710000_P01_ELECTRICAL_CAD (Autodesk Fusion 360 design; units mm, degrees)
description: ELECTRICAL | Điện | P01 | routes, pockets, grommets, power unit, hub zone
part number: 2026-10-31-23-39-13-770
description: ELECTRICAL - POWER UNIT - B2 | Điện - hộp nguồn - vách sau B2 | HS | P01
part number: 710001
description: ELECTRICAL - HARNESS - LIGHT FEED - B2/B4 | Điện - bó dây cấp đèn - vách sau | HS | P01
part number: 710011
description: ELECTRICAL - HARNESS - TRUNK - B2/R1 | Điện - bó dây chính - vách sau và vách phải | HS | P01
part number: 710021
description: ELECTRICAL - HARNESS - AIR COLUMN | Điện - bó dây cột gió | HS | P01
part number: 710023
description: ELECTRICAL - HARNESS - CALL LIGHT - R2 | Điện - bó dây đèn gọi video - vách phải trên | HS | P01
part number: 710024
description: ELECTRICAL - DRAW WIRE - CEILING ROUTE | Điện - dây mồi - đường trần | HS | P01
part number: 710031
description: ELECTRICAL - HUB AND CONTROLS ZONE | Điện - vùng cảm biến và nút bấm | HS | P01
part number: 710041
Autodesk Fusion 360 part; units mm, degrees
(part 1 of 2)
sketch "OUTLINE - PU" plane through (0, 0, 0) normal (0, 0, 1) x (1, 0, 0) in component "710001 ELECTRICAL - POWER UNIT - B2"
  line L0 (95, 766) -> (391, 766)
  line L1 (391, 766) -> (391, 838)
  line L2 (391, 838) -> (95, 838)
  line L3 (95, 838) -> (95, 766)
  dimension "d1608" = 296
  dimension "d1610" = 95
  dimension "d1611" = 766
  constraint horizontal L0
  constraint vertical L1
  constraint horizontal L2
  constraint vertical L3
  measures "d1608" horizontal distance of L0.start L0.end
  measures "d1610" horizontal distance of origin L0.start
  measures "d1611" vertical distance of origin L0.start
extrude "EXTRUDE - PU" add sketch "OUTLINE - PU" along normal blind 260 from surface at 870 makes body 1 in component "710001 ELECTRICAL - POWER UNIT - B2"
sketch "OUTLINE - PU-PLATE" plane through (0, 0, 0) normal (0, 0, 1) x (1, 0, 0) in component "710001 ELECTRICAL - POWER UNIT - B2"
  line L0 (83, 762.5) -> (403, 762.5)
  line L1 (403, 762.5) -> (403, 764)
  line L2 (403, 764) -> (83, 764)
  line L3 (83, 764) -> (83, 762.5)
  dimension "d1615" = 320
  dimension "d1617" = 83
  dimension "d1618" = 762.5
  constraint horizontal L0
  constraint vertical L1
  constraint horizontal L2
  constraint vertical L3
  measures "d1615" horizontal distance of L0.start L0.end
  measures "d1617" horizontal distance of origin L0.start
  measures "d1618" vertical distance of origin L0.start
extrude "EXTRUDE - PU-PLATE" add sketch "OUTLINE - PU-PLATE" along normal blind 284 from surface at 858 separate body makes body 2 in component "710001 ELECTRICAL - POWER UNIT - B2"
sketch "OUTLINE - INLET" plane through (0, 0, 0) normal (0, 1, 0) x (1, 0, 0) in component "710001 ELECTRICAL - POWER UNIT - B2"
  circle A0 centre (120, -313) radius 12
  dimension "d1622" = 24
  dimension "d1623" = 120
  dimension "d1624" = 313
  measures "d1622" diameter of A0
  measures "d1623" horizontal distance of origin A0.centre
  measures "d1624" vertical distance of origin A0.centre
extrude "EXTRUDE - INLET" add sketch "OUTLINE - INLET" along normal blind 35 from surface at 815 separate body makes body 3 in component "710001 ELECTRICAL - POWER UNIT - B2"
sketch "OUTLINE - LAN-FT" plane through (0, 0, 0) normal (0, 1, 0) x (1, 0, 0) in component "710001 ELECTRICAL - POWER UNIT - B2"
  circle A0 centre (120, -375) radius 12
  dimension "d1628" = 24
  dimension "d1629" = 120
  dimension "d1630" = 375
  measures "d1628" diameter of A0
  measures "d1629" horizontal distance of origin A0.centre
  measures "d1630" vertical distance of origin A0.centre
extrude "EXTRUDE - LAN-FT" add sketch "OUTLINE - LAN-FT" along normal blind 35 from surface at 815 separate body makes body 4 in component "710001 ELECTRICAL - POWER UNIT - B2"
sketch "OUTLINE - SLEEVE" plane through (0, 0, 0) normal (0, 0, 1) x (1, 0, 0) in component "710001 ELECTRICAL - POWER UNIT - B2"
  line L0 (140, 810) -> (160, 810)
  line L1 (160, 810) -> (160, 830)
  line L2 (160, 830) -> (140, 830)
  line L3 (140, 830) -> (140, 810)
  dimension "d1634" = 20
  dimension "d1635" = 20
  dimension "d1636" = 140
  dimension "d1637" = 810
  constraint horizontal L0
  constraint vertical L1
  constraint horizontal L2
  constraint vertical L3
  measures "d1634" horizontal distance of L0.start L0.end
  measures "d1635" vertical distance of L0.start L2.end
  measures "d1636" horizontal distance of origin L0.start
  measures "d1637" vertical distance of origin L0.start
extrude "EXTRUDE - SLEEVE" add sketch "OUTLINE - SLEEVE" along normal blind 569 from surface at 301 separate body makes body 5 in component "710001 ELECTRICAL - POWER UNIT - B2"
sketch "OUTLINE - P5" plane through (0, 0, 0) normal (0, 0, 1) x (1, 0, 0) in component "710011 ELECTRICAL - HARNESS - LIGHT FEED - B2/B4"
  line L0 (306, 779.5) -> (386, 779.5)
  line L1 (386, 779.5) -> (386, 795.5)
  line L2 (386, 795.5) -> (306, 795.5)
  line L3 (306, 795.5) -> (306, 779.5)
  dimension "d1643" = 306
  dimension "d1644" = 779.5
  constraint horizontal L0
  constraint vertical L1
  constraint horizontal L2
  constraint vertical L3
  measures "d1643" horizontal distance of origin L0.start
  measures "d1644" vertical distance of origin L0.start
extrude "EXTRUDE - P5" add sketch "OUTLINE - P5" along normal blind 80 from surface at 1134.5 separate body makes body 6 in component "710011 ELECTRICAL - HARNESS - LIGHT FEED - B2/B4"
sketch "OUTLINE - L1-B2" plane through (0, 0, 0) normal (0, 0, 1) x (1, 0, 0) in component "710011 ELECTRICAL - HARNESS - LIGHT FEED - B2/B4"
  line L0 (338, 779.5) -> (354, 779.5)
  line L1 (354, 779.5) -> (354, 795.5)
  line L2 (354, 795.5) -> (338, 795.5)
  line L3 (338, 795.5) -> (338, 779.5)
  dimension "d1650" = 338
  dimension "d1651" = 779.5
  constraint horizontal L0
  constraint vertical L1
  constraint horizontal L2
  constraint vertical L3
  measures "d1650" horizontal distance of origin L0.start
  measures "d1651" vertical distance of origin L0.start
extrude "EXTRUDE - L1-B2" add sketch "OUTLINE - L1-B2" along normal blind 15.87 from surface at 1214.5 separate body makes body 7 in component "710011 ELECTRICAL - HARNESS - LIGHT FEED - B2/B4"
sketch "OUTLINE - G-B2-B4" plane through (0, 0, 0) normal (0, 0, 1) x (1, 0, 0) in component "710011 ELECTRICAL - HARNESS - LIGHT FEED - B2/B4"
  circle A0 centre (346, 787.5) radius 9.55
  dimension "d1655" = 19.1
  dimension "d1656" = 346
  dimension "d1657" = 787.5
  measures "d1655" diameter of A0
  measures "d1656" horizontal distance of origin A0.centre
  measures "d1657" vertical distance of origin A0.centre
extrude "EXTRUDE - G-B2-B4" add sketch "OUTLINE - G-B2-B4" along normal blind 3.26 from surface at 1230.37 separate body makes body 8 in component "710011 ELECTRICAL - HARNESS - LIGHT FEED - B2/B4"
sketch "OUTLINE - P4" plane through (0, 0, 0) normal (0, 0, 1) x (1, 0, 0) in component "710011 ELECTRICAL - HARNESS - LIGHT FEED - B2/B4"
  line L0 (306, 779.5) -> (386, 779.5)
  line L1 (386, 779.5) -> (386, 795.5)
  line L2 (386, 795.5) -> (306, 795.5)
  line L3 (306, 795.5) -> (306, 779.5)
  dimension "d1663" = 306
  dimension "d1664" = 779.5
  constraint horizontal L0
  constraint vertical L1
  constraint horizontal L2
  constraint vertical L3
  measures "d1663" horizontal distance of origin L0.start
  measures "d1664" vertical distance of origin L0.start
extrude "EXTRUDE - P4" add sketch "OUTLINE - P4" along normal blind 150 from surface at 1233.63 separate body makes body 9 in component "710011 ELECTRICAL - HARNESS - LIGHT FEED - B2/B4"
sketch "OUTLINE - L1-B4" plane through (0, 0, 0) normal (0, 0, 1) x (1, 0, 0) in component "710011 ELECTRICAL - HARNESS - LIGHT FEED - B2/B4"
  line L0 (338, 779.5) -> (354, 779.5)
  line L1 (354, 779.5) -> (354, 795.5)
  line L2 (354, 795.5) -> (338, 795.5)
  line L3 (338, 795.5) -> (338, 779.5)
  dimension "d1670" = 338
  dimension "d1671" = 779.5
  constraint horizontal L0
  constraint vertical L1
  constraint horizontal L2
  constraint vertical L3
  measures "d1670" horizontal distance of origin L0.start
  measures "d1671" vertical distance of origin L0.start
extrude "EXTRUDE - L1-B4" add sketch "OUTLINE - L1-B4" along normal blind 806.37 from surface at 1383.63 separate body makes body 10 in component "710011 ELECTRICAL - HARNESS - LIGHT FEED - B2/B4"
sketch "OUTLINE - P6" plane through (0, 0, 0) normal (0, 0, 1) x (1, 0, 0) in component "710011 ELECTRICAL - HARNESS - LIGHT FEED - B2/B4"
  line L0 (306, 779.5) -> (386, 779.5)
  line L1 (386, 779.5) -> (386, 795.5)
  line L2 (386, 795.5) -> (306, 795.5)
  line L3 (306, 795.5) -> (306, 779.5)
  dimension "d1677" = 306
  dimension "d1678" = 779.5
  constraint horizontal L0
  constraint vertical L1
  constraint horizontal L2
  constraint vertical L3
  measures "d1677" horizontal distance of origin L0.start
  measures "d1678" vertical distance of origin L0.start
extrude "EXTRUDE - P6" add sketch "OUTLINE - P6" along normal blind 100 from surface at 2190 separate body makes body 11 in component "710011 ELECTRICAL - HARNESS - LIGHT FEED - B2/B4"
sketch "OUTLINE - FX-SHELF" plane through (0, 0, 0) normal (0, 1, 0) x (1, 0, 0) in component "710011 ELECTRICAL - HARNESS - LIGHT FEED - B2/B4"
  circle A0 centre (346, -2250) radius 8
  dimension "d1682" = 16
  dimension "d1683" = 346
  dimension "d1684" = 2250
  measures "d1682" diameter of A0
  measures "d1683" horizontal distance of origin A0.centre
  measures "d1684" vertical distance of origin A0.centre
extrude "EXTRUDE - FX-SHELF" add sketch "OUTLINE - FX-SHELF" along normal blind 9.5 from surface at 766 separate body makes body 12 in component "710011 ELECTRICAL - HARNESS - LIGHT FEED - B2/B4"
sketch "OUTLINE - P1" plane through (0, 0, 0) normal (0, 0, 1) x (1, 0, 0) in component "710021 ELECTRICAL - HARNESS - TRUNK - B2/R1"
  line L0 (395.5, 779.5) -> (545.5, 779.5)
  line L1 (545.5, 779.5) -> (545.5, 795.5)
  line L2 (545.5, 795.5) -> (395.5, 795.5)
  line L3 (395.5, 795.5) -> (395.5, 779.5)
  dimension "d1688" = 150
  dimension "d1690" = 395.5
  dimension "d1691" = 779.5
  constraint horizontal L0
  constraint vertical L1
  constraint horizontal L2
  constraint vertical L3
  measures "d1688" horizontal distance of L0.start L0.end
  measures "d1690" horizontal distance of origin L0.start
  measures "d1691" vertical distance of origin L0.start
extrude "EXTRUDE - P1" add sketch "OUTLINE - P1" along normal blind 80 from surface at 1060 separate body makes body 13 in component "710021 ELECTRICAL - HARNESS - TRUNK - B2/R1"
sketch "OUTLINE - T1-B2" plane through (0, 0, 0) normal (0, 0, 1) x (1, 0, 0) in component "710021 ELECTRICAL - HARNESS - TRUNK - B2/R1"
  line L0 (545.5, 779.5) -> (1163.5, 779.5)
  line L1 (1163.5, 779.5) -> (1163.5, 795.5)
  line L2 (1163.5, 795.5) -> (545.5, 795.5)
  line L3 (545.5, 795.5) -> (545.5, 779.5)
  dimension "d1695" = 618
  dimension "d1697" = 545.5
  dimension "d1698" = 779.5
  constraint horizontal L0
  constraint vertical L1
  constraint horizontal L2
  constraint vertical L3
  measures "d1695" horizontal distance of L0.start L0.end
  measures "d1697" horizontal distance of origin L0.start
  measures "d1698" vertical distance of origin L0.start
extrude "EXTRUDE - T1-B2" add sketch "OUTLINE - T1-B2" along normal blind 30 from surface at 1085 separate body makes body 14 in component "710021 ELECTRICAL - HARNESS - TRUNK - B2/R1"
sketch "OUTLINE - FS-CNR" plane through (0, 0, 0) normal (0, 0, 1) x (1, 0, 0) in component "710021 ELECTRICAL - HARNESS - TRUNK - B2/R1"
  line L0 (1166, 768) -> (1175.5, 768)
  line L1 (1175.5, 768) -> (1175.5, 786)
  line L2 (1175.5, 786) -> (1166, 786)
  line L3 (1166, 786) -> (1166, 768)
  dimension "d1703" = 18
  dimension "d1704" = 1166
  dimension "d1705" = 768
  constraint horizontal L0
  constraint vertical L1
  constraint horizontal L2
  constraint vertical L3
  measures "d1703" vertical distance of L0.start L2.end
  measures "d1704" horizontal distance of origin L0.start
  measures "d1705" vertical distance of origin L0.start
extrude "EXTRUDE - FS-CNR" add sketch "OUTLINE - FS-CNR" along normal blind 120 from surface at 1040 separate body makes body 15 in component "710021 ELECTRICAL - HARNESS - TRUNK - B2/R1"
sketch "OUTLINE - P2" plane through (0, 0, 0) normal (0, 0, 1) x (1, 0, 0) in component "710021 ELECTRICAL - HARNESS - TRUNK - B2/R1"
  line L0 (1179.5, 637) -> (1195.5, 637)
  line L1 (1195.5, 637) -> (1195.5, 787)
  line L2 (1195.5, 787) -> (1179.5, 787)
  line L3 (1179.5, 787) -> (1179.5, 637)
  dimension "d1711" = 1179.5
  dimension "d1712" = 637
  constraint horizontal L0
  constraint vertical L1
  constraint horizontal L2
  constraint vertical L3
  measures "d1711" horizontal distance of origin L0.start
  measures "d1712" vertical distance of origin L0.start
extrude "EXTRUDE - P2" add sketch "OUTLINE - P2" along normal blind 80 from surface at 1060 separate body makes body 16 in component "710021 ELECTRICAL - HARNESS - TRUNK - B2/R1"
sketch "OUTLINE - S-CNR" plane through (0, 0, 0) normal (0, 0, 1) x (1, 0, 0) in component "710021 ELECTRICAL - HARNESS - TRUNK - B2/R1"
  line L0 (1163.5, 776) -> (1166, 776)
  line L1 (1166, 776) -> (1166, 787)
  line L2 (1166, 787) -> (1163.5, 787)
  line L3 (1163.5, 787) -> (1163.5, 776)
  dimension "d1718" = 1163.5
  dimension "d1719" = 776
  constraint horizontal L0
  constraint vertical L1
  constraint horizontal L2
  constraint vertical L3
  measures "d1718" horizontal distance of origin L0.start
  measures "d1719" vertical distance of origin L0.start
extrude "EXTRUDE - S-CNR" add sketch "OUTLINE - S-CNR" along normal blind 80 from surface at 1060 separate body makes body 17 in component "710021 ELECTRICAL - HARNESS - TRUNK - B2/R1"
sketch "OUTLINE - T1-R1A" plane through (0, 0, 0) normal (0, 0, 1) x (1, 0, 0) in component "710021 ELECTRICAL - HARNESS - TRUNK - B2/R1"
  line L0 (1179.5, 315.5) -> (1195.5, 315.5)
  line L1 (1195.5, 315.5) -> (1195.5, 637)
  line L2 (1195.5, 637) -> (1179.5, 637)
  line L3 (1179.5, 637) -> (1179.5, 315.5)
  dimension "d1724" = 321.5
  dimension "d1725" = 1179.5
  dimension "d1726" = 315.5
  constraint horizontal L0
  constraint vertical L1
  constraint horizontal L2
  constraint vertical L3
  measures "d1724" vertical distance of L0.start L2.end
  measures "d1725" horizontal distance of origin L0.start
  measures "d1726" vertical distance of origin L0.start
extrude "EXTRUDE - T1-R1A" add sketch "OUTLINE - T1-R1A" along normal blind 30 from surface at 1085 separate body makes body 18 in component "710021 ELECTRICAL - HARNESS - TRUNK - B2/R1"
sketch "OUTLINE - P3-KIT" plane through (0, 0, 0) normal (0, 0, 1) x (1, 0, 0) in component "710021 ELECTRICAL - HARNESS - TRUNK - B2/R1"
  line L0 (1179.5, 165.5) -> (1195.5, 165.5)
  line L1 (1195.5, 165.5) -> (1195.5, 315.5)
  line L2 (1195.5, 315.5) -> (1179.5, 315.5)
  line L3 (1179.5, 315.5) -> (1179.5, 165.5)
  dimension "d1731" = 150
  dimension "d1732" = 1179.5
  dimension "d1733" = 165.5
  constraint horizontal L0
  constraint vertical L1
  constraint horizontal L2
  constraint vertical L3
  measures "d1731" vertical distance of L0.start L2.end
  measures "d1732" horizontal distance of origin L0.start
  measures "d1733" vertical distance of origin L0.start
extrude "EXTRUDE - P3-KIT" add sketch "OUTLINE - P3-KIT" along normal blind 150 from surface at 1085 separate body makes body 19 in component "710021 ELECTRICAL - HARNESS - TRUNK - B2/R1"
sketch "OUTLINE - FA-KIT" plane through (0, 0, 0) normal (1, 0, 0) x (0, 0, -1) in component "710021 ELECTRICAL - HARNESS - TRUNK - B2/R1"
  circle A0 centre (-1180, 240.5) radius 30
  dimension "d1737" = 60
  dimension "d1738" = 240.5
  dimension "d1739" = 1180
  measures "d1737" diameter of A0
  measures "d1738" vertical distance of origin A0.centre
  measures "d1739" horizontal distance of origin A0.centre
extrude "EXTRUDE - FA-KIT" add sketch "OUTLINE - FA-KIT" along normal blind 9.5 from surface at 1166 separate body makes body 20 in component "710021 ELECTRICAL - HARNESS - TRUNK - B2/R1"
sketch "OUTLINE - T1-R1B" plane through (0, 0, 0) normal (0, 0, 1) x (1, 0, 0) in component "710021 ELECTRICAL - HARNESS - TRUNK - B2/R1"
  line L0 (1179.5, -307.55) -> (1195.5, -307.55)
  line L1 (1195.5, -307.55) -> (1195.5, 165.5)
  line L2 (1195.5, 165.5) -> (1179.5, 165.5)
  line L3 (1179.5, 165.5) -> (1179.5, -307.55)
  dimension "d1744" = 473.05
  dimension "d1745" = 1179.5
  dimension "d1746" = 307.55
  constraint horizontal L0
  constraint vertical L1
  constraint horizontal L2
  constraint vertical L3
  measures "d1744" vertical distance of L0.start L2.end
  measures "d1745" horizontal distance of origin L0.start
  measures "d1746" vertical distance of origin L0.start
extrude "EXTRUDE - T1-R1B" add sketch "OUTLINE - T1-R1B" along normal blind 30 from surface at 1085 separate body makes body 21 in component "710021 ELECTRICAL - HARNESS - TRUNK - B2/R1"
sketch "OUTLINE - FX-COL" plane through (0, 0, 0) normal (1, 0, 0) x (0, 0, -1) in component "710021 ELECTRICAL - HARNESS - TRUNK - B2/R1"
  circle A0 centre (-1100, -298) radius 9.55
  dimension "d1750" = 19.1
  dimension "d1751" = 298
  dimension "d1752" = 1100
  measures "d1750" diameter of A0
  measures "d1751" vertical distance of origin A0.centre
  measures "d1752" horizontal distance of origin A0.centre
extrude "EXTRUDE - FX-COL" add sketch "OUTLINE - FX-COL" along normal blind 11.5 from surface at 1164 separate body makes body 22 in component "710021 ELECTRICAL - HARNESS - TRUNK - B2/R1"
sketch "OUTLINE - CHASE" plane through (0, 0, 0) normal (0, 0, 1) x (1, 0, 0) in component "710023 ELECTRICAL - HARNESS - AIR COLUMN"
  line L0 (1140, -310) -> (1164, -310)
  line L1 (1164, -310) -> (1164, -286)
  line L2 (1164, -286) -> (1140, -286)
  line L3 (1140, -286) -> (1140, -310)
  dimension "d1757" = 24
  dimension "d1758" = 1140
  dimension "d1759" = 310
  constraint horizontal L0
  constraint vertical L1
  constraint horizontal L2
  constraint vertical L3
  measures "d1757" vertical distance of L0.start L2.end
  measures "d1758" horizontal distance of origin L0.start
  measures "d1759" vertical distance of origin L0.start
extrude "EXTRUDE - CHASE" add sketch "OUTLINE - CHASE" along normal blind 1037.1 from surface at 1080.9 separate body makes body 23 in component "710023 ELECTRICAL - HARNESS - AIR COLUMN"
sketch "OUTLINE - TO-DR" plane through (0, 0, 0) normal (0, 0, 1) x (1, 0, 0) in component "710023 ELECTRICAL - HARNESS - AIR COLUMN"
  line L0 (1140, -643) -> (1164, -643)
  line L1 (1164, -643) -> (1164, -310)
  line L2 (1164, -310) -> (1140, -310)
  line L3 (1140, -310) -> (1140, -643)
  dimension "d1764" = 333
  dimension "d1765" = 1140
  dimension "d1766" = 643
  constraint horizontal L0
  constraint vertical L1
  constraint horizontal L2
  constraint vertical L3
  measures "d1764" vertical distance of L0.start L2.end
  measures "d1765" horizontal distance of origin L0.start
  measures "d1766" vertical distance of origin L0.start
extrude "EXTRUDE - TO-DR" add sketch "OUTLINE - TO-DR" along normal blind 16 from surface at 2100 separate body makes body 24 in component "710023 ELECTRICAL - HARNESS - AIR COLUMN"
sketch "OUTLINE - G-DR" plane through (0, 0, 0) normal (0, 1, 0) x (1, 0, 0) in component "710023 ELECTRICAL - HARNESS - AIR COLUMN"
  circle A0 centre (1152, -2108) radius 9.55
  dimension "d1770" = 19.1
  dimension "d1771" = 1152
  dimension "d1772" = 2108
  measures "d1770" diameter of A0
  measures "d1771" horizontal distance of origin A0.centre
  measures "d1772" vertical distance of origin A0.centre
extrude "EXTRUDE - G-DR" add sketch "OUTLINE - G-DR" along normal blind 4 from surface at -647 separate body makes body 25 in component "710023 ELECTRICAL - HARNESS - AIR COLUMN"
sketch "OUTLINE - IN-DR" plane through (0, 0, 0) normal (0, 0, 1) x (1, 0, 0) in component "710023 ELECTRICAL - HARNESS - AIR COLUMN"
  line L0 (1140, -665) -> (1164, -665)
  line L1 (1164, -665) -> (1164, -647)
  line L2 (1164, -647) -> (1140, -647)
  line L3 (1140, -647) -> (1140, -665)
  dimension "d1777" = 18
  dimension "d1778" = 1140
  dimension "d1779" = 665
  constraint horizontal L0
  constraint vertical L1
  constraint horizontal L2
  constraint vertical L3
  measures "d1777" vertical distance of L0.start L2.end
  measures "d1778" horizontal distance of origin L0.start
  measures "d1779" vertical distance of origin L0.start
extrude "EXTRUDE - IN-DR" add sketch "OUTLINE - IN-DR" along normal blind 16 from surface at 2100 separate body makes body 26 in component "710023 ELECTRICAL - HARNESS - AIR COLUMN"
sketch "OUTLINE - G-SOFFIT" plane through (0, 0, 0) normal (0, 0, 1) x (1, 0, 0) in component "710023 ELECTRICAL - HARNESS - AIR COLUMN"
  circle A0 centre (1152, -298) radius 9.55
  dimension "d1783" = 19.1
  dimension "d1784" = 1152
  dimension "d1785" = 298
  measures "d1783" diameter of A0
  measures "d1784" horizontal distance of origin A0.centre
  measures "d1785" vertical distance of origin A0.centre
extrude "EXTRUDE - G-SOFFIT" add sketch "OUTLINE - G-SOFFIT" along normal blind 4 from surface at 2118 separate body makes body 27 in component "710023 ELECTRICAL - HARNESS - AIR COLUMN"
sketch "OUTLINE - TO-SOFFIT" plane through (0, 0, 0) normal (0, 0, 1) x (1, 0, 0) in component "710023 ELECTRICAL - HARNESS - AIR COLUMN"
  line L0 (1140, -310) -> (1164, -310)
  line L1 (1164, -310) -> (1164, -286)
  line L2 (1164, -286) -> (1140, -286)
  line L3 (1140, -286) -> (1140, -310)
  dimension "d1790" = 24
  dimension "d1791" = 1140
  dimension "d1792" = 310
  constraint horizontal L0
  constraint vertical L1
  constraint horizontal L2
  constraint vertical L3
  measures "d1790" vertical distance of L0.start L2.end
  measures "d1791" horizontal distance of origin L0.start
  measures "d1792" vertical distance of origin L0.start
extrude "EXTRUDE - TO-SOFFIT" add sketch "OUTLINE - TO-SOFFIT" along normal blind 38 from surface at 2122 separate body makes body 28 in component "710023 ELECTRICAL - HARNESS - AIR COLUMN"
sketch "OUTLINE - HUB" plane through (0, 0, 0) normal (0, 0, 1) x (1, 0, 0) in component "710041 ELECTRICAL - HUB AND CONTROLS ZONE"
  line L0 (957, -315) -> (1137, -315)
  line L1 (1137, -315) -> (1137, -285)
  line L2 (1137, -285) -> (957, -285)
  line L3 (957, -285) -> (957, -315)
  dimension "d1796" = 180
  dimension "d1797" = 30
  dimension "d1798" = 957
  dimension "d1799" = 315
  constraint horizontal L0
  constraint vertical L1
  constraint horizontal L2
  constraint vertical L3
  measures "d1796" horizontal distance of L0.start L0.end
  measures "d1797" vertical distance of L0.start L2.end
  measures "d1798" horizontal distance of origin L0.start
  measures "d1799" vertical distance of origin L0.start
extrude "EXTRUDE - HUB" add sketch "OUTLINE - HUB" along normal blind 180 from surface at 1110 separate body makes body 29 in component "710041 ELECTRICAL - HUB AND CONTROLS ZONE"
sketch "OUTLINE - FX-CALL0" plane through (0, 0, 0) normal (1, 0, 0) x (0, 0, -1) in component "710024 ELECTRICAL - HARNESS - CALL LIGHT - R2"
  circle A0 centre (-2250, -209.5) radius 6
  dimension "d1803" = 12
  dimension "d1804" = 209.5
  dimension "d1805" = 2250
  measures "d1803" diameter of A0
  measures "d1804" vertical distance of origin A0.centre
  measures "d1805" horizontal distance of origin A0.centre
extrude "EXTRUDE - FX-CALL0" add sketch "OUTLINE - FX-CALL0" along normal blind 9.5 from surface at 1166 separate body makes body 30 in component "710024 ELECTRICAL - HARNESS - CALL LIGHT - R2"
sketch "OUTLINE - P7" plane through (0, 0, 0) normal (0, 0, 1) x (1, 0, 0) in component "710024 ELECTRICAL - HARNESS - CALL LIGHT - R2"
  line L0 (1179.5, -249.5) -> (1195.5, -249.5)
  line L1 (1195.5, -249.5) -> (1195.5, -169.5)
  line L2 (1195.5, -169.5) -> (1179.5, -169.5)
  line L3 (1179.5, -169.5) -> (1179.5, -249.5)
  dimension "d1811" = 1179.5
  dimension "d1812" = 249.5
  constraint horizontal L0
  constraint vertical L1
  constraint horizontal L2
  constraint vertical L3
  measures "d1811" horizontal distance of origin L0.start
  measures "d1812" vertical distance of origin L0.start
extrude "EXTRUDE - P7" add sketch "OUTLINE - P7" along normal blind 150 from surface at 2094 separate body makes body 31 in component "710024 ELECTRICAL - HARNESS - CALL LIGHT - R2"
sketch "OUTLINE - CALL-R2" plane through (0, 0, 0) normal (0, 0, 1) x (1, 0, 0) in component "710024 ELECTRICAL - HARNESS - CALL LIGHT - R2"
  line L0 (1179.5, -217.5) -> (1195.5, -217.5)
  line L1 (1195.5, -217.5) -> (1195.5, -201.5)
  line L2 (1195.5, -201.5) -> (1179.5, -201.5)
  line L3 (1179.5, -201.5) -> (1179.5, -217.5)
  dimension "d1818" = 1179.5
  dimension "d1819" = 217.5
  constraint horizontal L0
  constraint vertical L1
  constraint horizontal L2
  constraint vertical L3
  measures "d1818" horizontal distance of origin L0.start
  measures "d1819" vertical distance of origin L0.start
extrude "EXTRUDE - CALL-R2" add sketch "OUTLINE - CALL-R2" along normal blind 638 from surface at 1456 separate body makes body 32 in component "710024 ELECTRICAL - HARNESS - CALL LIGHT - R2"
sketch "OUTLINE - FX-CALL2" plane through (0, 0, 0) normal (1, 0, 0) x (0, 0, -1) in component "710024 ELECTRICAL - HARNESS - CALL LIGHT - R2"
  circle A0 centre (-1450, -209.5) radius 6
  dimension "d1823" = 12
  dimension "d1824" = 209.5
  dimension "d1825" = 1450
  measures "d1823" diameter of A0
  measures "d1824" vertical distance of origin A0.centre
  measures "d1825" horizontal distance of origin A0.centre
extrude "EXTRUDE - FX-CALL2" add sketch "OUTLINE - FX-CALL2" along normal blind 9.5 from surface at 1166 separate body makes body 33 in component "710024 ELECTRICAL - HARNESS - CALL LIGHT - R2"
sketch "OUTLINE - C1-UP" plane through (0, 0, 0) normal (0, 0, 1) x (1, 0, 0) in component "710031 ELECTRICAL - DRAW WIRE - CEILING ROUTE"
  line L0 (342, 783.5) -> (350, 783.5)
  line L1 (350, 783.5) -> (350, 791.5)
  line L2 (350, 791.5) -> (342, 791.5)
  line L3 (342, 791.5) -> (342, 783.5)
  dimension "d1831" = 342
  dimension "d1832" = 783.5
  constraint horizontal L0
  constraint vertical L1
  constraint horizontal L2
  constraint vertical L3
  measures "d1831" horizontal distance of origin L0.start
  measures "d1832" vertical distance of origin L0.start
extrude "EXTRUDE - C1-UP" add sketch "OUTLINE - C1-UP" along normal blind 22 from surface at 2290 separate body makes body 34 in component "710031 ELECTRICAL - DRAW WIRE - CEILING ROUTE"
sketch "OUTLINE - C1-JOG" plane through (0, 0, 0) normal (0, 0, 1) x (1, 0, 0) in component "710031 ELECTRICAL - DRAW WIRE - CEILING ROUTE"
  line L0 (342, 783.5) -> (587, 783.5)
  line L1 (587, 783.5) -> (587, 791.5)
  line L2 (587, 791.5) -> (342, 791.5)
  line L3 (342, 791.5) -> (342, 783.5)
  dimension "d1838" = 342
  dimension "d1839" = 783.5
  constraint horizontal L0
  constraint vertical L1
  constraint horizontal L2
  constraint vertical L3
  measures "d1838" horizontal distance of origin L0.start
  measures "d1839" vertical distance of origin L0.start
extrude "EXTRUDE - C1-JOG" add sketch "OUTLINE - C1-JOG" along normal blind 8 from surface at 2312 separate body makes body 35 in component "710031 ELECTRICAL - DRAW WIRE - CEILING ROUTE"
sketch "OUTLINE - C1-RISE" plane through (0, 0, 0) normal (0, 0, 1) x (1, 0, 0) in component "710031 ELECTRICAL - DRAW WIRE - CEILING ROUTE"
  line L0 (579, 783.5) -> (587, 783.5)
  line L1 (587, 783.5) -> (587, 791.5)
  line L2 (587, 791.5) -> (579, 791.5)
  line L3 (579, 791.5) -> (579, 783.5)
  dimension "d1845" = 579
  dimension "d1846" = 783.5
  constraint horizontal L0
  constraint vertical L1
  constraint horizontal L2
  constraint vertical L3
  measures "d1845" horizontal distance of origin L0.start
  measures "d1846" vertical distance of origin L0.start
extrude "EXTRUDE - C1-RISE" add sketch "OUTLINE - C1-RISE" along normal blind 14 from surface at 2320 separate body makes body 36 in component "710031 ELECTRICAL - DRAW WIRE - CEILING ROUTE"
sketch "OUTLINE - FX-CEIL" plane through (0, 0, 0) normal (0, 1, 0) x (1, 0, 0) in component "710031 ELECTRICAL - DRAW WIRE - CEILING ROUTE"
  circle A0 centre (583, -2330) radius 6
  dimension "d1850" = 12
  dimension "d1851" = 583
  dimension "d1852" = 2330
  measures "d1850" diameter of A0
  measures "d1851" horizontal distance of origin A0.centre
  measures "d1852" vertical distance of origin A0.centre
extrude "EXTRUDE - FX-CEIL" add sketch "OUTLINE - FX-CEIL" along normal blind 9.5 from surface at 766 separate body makes body 37 in component "710031 ELECTRICAL - DRAW WIRE - CEILING ROUTE"
sketch "OUTLINE - G-CEIL-B" plane through (0, 0, 0) normal (0, 1, 0) x (1, 0, 0) in component "710031 ELECTRICAL - DRAW WIRE - CEILING ROUTE"
  circle A0 centre (583, -2330) radius 9.55
  dimension "d1856" = 19.1
  dimension "d1857" = 583
  dimension "d1858" = 2330
  measures "d1856" diameter of A0
  measures "d1857" horizontal distance of origin A0.centre
  measures "d1858" vertical distance of origin A0.centre
extrude "EXTRUDE - G-CEIL-B" add sketch "OUTLINE - G-CEIL-B" along normal blind 3.5 from surface at 762.5 separate body makes body 38 in component "710031 ELECTRICAL - DRAW WIRE - CEILING ROUTE"
sketch "OUTLINE - C1-CEIL" plane through (0, 0, 0) normal (0, 0, 1) x (1, 0, 0) in component "710031 ELECTRICAL - DRAW WIRE - CEILING ROUTE"
  line L0 (579, -281.5) -> (587, -281.5)
  line L1 (587, -281.5) -> (587, 762.5)
  line L2 (587, 762.5) -> (579, 762.5)
  line L3 (579, 762.5) -> (579, -281.5)
  dimension "d1863" = 1044
  dimension "d1864" = 579
  dimension "d1865" = 281.5
  constraint horizontal L0
  constraint vertical L1
  constraint horizontal L2
  constraint vertical L3
  measures "d1863" vertical distance of L0.start L2.end
  measures "d1864" horizontal distance of origin L0.start
  measures "d1865" vertical distance of origin L0.start
extrude "EXTRUDE - C1-CEIL" add sketch "OUTLINE - C1-CEIL" along normal blind 15.5 from surface at 2326 separate body makes body 39 in component "710031 ELECTRICAL - DRAW WIRE - CEILING ROUTE"
sketch "OUTLINE - G-CEIL-F" plane through (0, 0, 0) normal (0, 1, 0) x (1, 0, 0) in component "710031 ELECTRICAL - DRAW WIRE - CEILING ROUTE"
  circle A0 centre (583, -2337.5) radius 9.55
  dimension "d1869" = 19.1
  dimension "d1870" = 583
  dimension "d1871" = 2337.5
  measures "d1869" diameter of A0
  measures "d1870" horizontal distance of origin A0.centre
  measures "d1871" vertical distance of origin A0.centre
extrude "EXTRUDE - G-CEIL-F" add sketch "OUTLINE - G-CEIL-F" along normal blind 3.5 from surface at -285 separate body makes body 40 in component "710031 ELECTRICAL - DRAW WIRE - CEILING ROUTE"
component "710001 ELECTRICAL - POWER UNIT - B2" placed x (1, 0, 0) y (0, 1, 0) z (0, 0, 1) at (0, 0, 0)
component "710011 ELECTRICAL - HARNESS - LIGHT FEED - B2/B4" placed x (1, 0, 0) y (0, 1, 0) z (0, 0, 1) at (0, 0, 0)
component "710021 ELECTRICAL - HARNESS - TRUNK - B2/R1" placed x (1, 0, 0) y (0, 1, 0) z (0, 0, 1) at (0, 0, 0)
component "710023 ELECTRICAL - HARNESS - AIR COLUMN" placed x (1, 0, 0) y (0, 1, 0) z (0, 0, 1) at (0, 0, 0)
component "710024 ELECTRICAL - HARNESS - CALL LIGHT - R2" placed x (1, 0, 0) y (0, 1, 0) z (0, 0, 1) at (0, 0, 0)
component "710031 ELECTRICAL - DRAW WIRE - CEILING ROUTE" placed x (1, 0, 0) y (0, 1, 0) z (0, 0, 1) at (0, 0, 0)
component "710041 ELECTRICAL - HUB AND CONTROLS ZONE" placed x (1, 0, 0) y (0, 1, 0) z (0, 0, 1) at (0, 0, 0)
equation "pod_w = pod_w_Ref" comment "SOURCE: skeleton P04 pod_w, derived (100000_P04_POD-SKELETON_CAD)"
equation "pod_d = pod_d_Ref" comment "SOURCE: skeleton P04 pod_d, derived (100000_P04_POD-SKELETON_CAD)"
equation "pod_h = pod_h_Ref" comment "SOURCE: skeleton P04 pod_h, derived (100000_P04_POD-SKELETON_CAD)"
equation "outer_t = outer_t_Ref" comment "SOURCE: skeleton P04 outer_t, derived (100000_P04_POD-SKELETON_CAD)"
equation "cav_gap = cav_gap_Ref" comment "SOURCE: skeleton P04 cav_gap, derived (100000_P04_POD-SKELETON_CAD)"
equation "cass_t = cass_t_Ref" comment "SOURCE: skeleton P04 cass_t, derived (100000_P04_POD-SKELETON_CAD)"
equation "stack_t = stack_t_Ref" comment "SOURCE: skeleton P04 stack_t, derived (100000_P04_POD-SKELETON_CAD)"
equation "seam_gap = seam_gap_Ref" comment "SOURCE: skeleton P04 seam_gap, derived (100000_P04_POD-SKELETON_CAD)"
equation "lin_gap = lin_gap_Ref" comment "SOURCE: skeleton P04 lin_gap, derived (100000_P04_POD-SKELETON_CAD)"
equation "wall_depth = wall_depth_Ref" comment "SOURCE: skeleton P04 wall_depth, derived (100000_P04_POD-SKELETON_CAD)"
equation "side_h = side_h_Ref" comment "SOURCE: skeleton P04 side_h, derived (100000_P04_POD-SKELETON_CAD)"
equation "back_ph = back_ph_Ref" comment "SOURCE: skeleton P04 back_ph, derived (100000_P04_POD-SKELETON_CAD)"
equation "back_oh = back_oh_Ref" comment "SOURCE: skeleton P04 back_oh, derived (100000_P04_POD-SKELETON_CAD)"
equation "half_pw = half_pw_Ref" comment "SOURCE: skeleton P04 half_pw, derived (100000_P04_POD-SKELETON_CAD)"
equation "panel_z0 = panel_z0_Ref" comment "SOURCE: skeleton P04 panel_z0, derived (100000_P04_POD-SKELETON_CAD)"
equation "tray_t = 0.5 mm" comment "CONFIRMED: D-37: the cassette tray is 0.5 mm galvanised steel"
equation "felt_t = 9 mm" comment "CONFIRMED: D-17, REQ-BLD-01: 9 mm PET felt on the cassette face"
equation "gap_in = cass_t - felt_t - 2 * tray_t" comment "CALCULATION: the cassette's air gap between the felt (on its 0.5 mm lips) and the tray base: 34 - 9 - 1 = 24 (as CEILING's gap_h)"
equation "lip_w = 12 mm" comment "CONFIRMED: D-69: 12 mm lips hold the felt at the cassette edges; no cable hole goes through a lip except where named"
equation "y_bf = pod_d / 2 - stack_t" comment "CALCULATION: back wall lining: felt face plane Y 766"
equation "y_bg = y_bf + tray_t + felt_t + gap_in / 2" comment "CALCULATION: back wall lining: middle of the cable gap, Y 787.5"
equation "x_rf = pod_w / 2 - stack_t" comment "CALCULATION: right wall lining: felt face plane X 1166"
equation "x_rg = x_rf + tray_t + felt_t + gap_in / 2" comment "CALCULATION: right wall lining: middle of the cable gap, X 1187.5"
equation "z_cf = pod_h - stack_t" comment "CALCULATION: ceiling lining: felt face plane Z 2316"
equation "z_cg = z_cf + tray_t + felt_t + gap_in / 2" comment "CALCULATION: ceiling lining: middle of the cable gap, Z 2337.5 (CEILING's cable holes sit here)"
equation "z_b2t = panel_z0 + back_ph" comment "CALCULATION: top of the lower back lining B2-CASS, Z 1230.87"
equation "z_b4b = panel_z0 + back_ph + seam_gap" comment "CALCULATION: bottom of the upper back lining B4-CASS, Z 1233.13"
equation "z_r1t = panel_z0 + side_h" comment "CALCULATION: top of the lower side lining R1-CASS, Z 1255"
equation "rt_h = 8 mm" comment "ASSUMPTION: half the depth of a cable bundle in the 24 mm gap (16 deep), leaving 4 mm each side for the clips"
equation "rt_w = 30 mm" comment "ASSUMPTION: width of the trunk bundle laid flat: air feed, cockpit feed, signal cable, Cat6"
equation "dw_h = 4 mm" comment "ASSUMPTION: half the size of a draw-wire reserve (8 x 8)"
equation "pk_l = 150 mm" comment "ASSUMPTION: length of a connector pocket: a mated plug pair and 100 mm of slack loop"
equation "pk_h = 40 mm" comment "ASSUMPTION: half the width of a connector pocket (80)"
equation "grm_d = 19.1 mm" comment "SOURCE: Heyco 2836 Shorty Bushing SB 750-625: 19.1 mm hole, panels to 1.6 mm, passes 15.9 mm (maker page, read 2026-10-31); 0.5 mm fit HOLD H-ELE-01"
equation "grm_s = 12 mm" comment "ASSUMPTION: felt-only hole for a single cable (no steel, so no bushing)"
equation "grm_c = 2 mm" comment "ASSUMPTION: grommet envelope: space taken on the pocket side of a return"
equation "slot_h = 10.000000 mm" comment "ASSUMPTION: half the height of the grommeted slot in the cut-out's right return (20 x 70): the RJ45 and 6-way plugs pass it on site"
equation "slot_l = 70.000000 mm" comment "ASSUMPTION: length of that slot along Z: passes both lead exits of the unit (40 mm apart, Ø19.1 bushings) with about 5 mm each end"
equation "pu_w = 296 mm" comment "ASSUMPTION: power unit width (X): two 86 x 86 plates side by side, the RCBO window and the vents; narrowed by 4 mm so its right side (X 391) clears B2's first stud (X 395.75) by 4.75 mm (WALL, through the PM, 2026-10-31)"
equation "pu_h = 260 mm" comment "ASSUMPTION: power unit height (Z): plates over the RCBO window, the three supplies behind"
equation "pu_d = 72 mm" comment "CALCULATION: power unit depth (Y) from the felt face: 78 to the frame's skin side (84 - 3 ACP - 3 bond line) less 6 clear"
equation "pu_x0 = 95 mm" comment "ASSUMPTION: power unit left side: clear of the B1-B2 closing seam member (X 1.13-21.13) and its pin-bolt pocket (to X 81); WALL confirms the bay"
equation "pu_zc = 1000 mm" comment "DECIDED: PM ruling 2026-10-31 in the ELECTRICAL group: the user socket and LAN at the ledge height, about 1000 mm (D-70); v1's plates were at Z 1066"
equation "pu_clr = 4 mm" comment "ASSUMPTION: gap between the frame-mounted unit and the floating B2 cassette's cut-out, so the lining stays floating (= cav_gap)"
equation "pu_x1 = pu_x0 + pu_w" comment "CALCULATION: power unit right side, X 391"
equation "pu_z0 = pu_zc - pu_h / 2" comment "CALCULATION: power unit bottom, Z 870"
equation "pu_z1 = pu_zc + pu_h / 2" comment "CALCULATION: power unit top, Z 1130"
equation "cut_x1 = pu_x1 + pu_clr" comment "CALCULATION: B2-CASS cut-out: its right return, X 395"
equation "cut_z1 = pu_z1 + pu_clr" comment "CALCULATION: B2-CASS cut-out: its top return, Z 1134"
equation "lt_x = pu_x1 - 45 mm" comment "ASSUMPTION: light feed leaves the unit's top 45 mm in from its right side, X 346: its Ø19.1 exit more than 2 diameters from the top's corner relief (C09)"
equation "inlet_x = 120 mm" comment "ASSUMPTION: v1's inlet sits at X 0, which is now the B1-B2 closing seam (D-65); it moves into B2 just clear of the seam member and its pin-bolt pocket"
equation "inlet_z = 313 mm" comment "SOURCE: v1 STEP 'Power Jack' centre Z(v1) 298.3 + 15 (conventions section 4)"
equation "lan_z = 375 mm" comment "SOURCE: v1 STEP 'Jack LAN' centre Z(v1) 360 + 15"
equation "inlet_d = 24 mm" comment "SOURCE: powerCON TRUE1 TOP cut-out Ø23.8 (selection E); etherCON NE8FDP Ø24"
equation "inlet_l = 35 mm" comment "SOURCE: depth behind the skin: powerCON TRUE1 TOP 31.2 mm behind its 4.5 mm flange; etherCON NE8FDP 34.55 mm (Neutrik drawings, read 2026-10-31)"
equation "sl_x = inlet_x + 30 mm" comment "CALCULATION: mains and LAN sleeve, beside the inlet column, X 150 (centre): its entry hole in the unit's bottom 2 diameters from the corner relief (C09)"
equation "sl_y = pod_d / 2 - 30 mm" comment "CALCULATION: sleeve centre in the frame bay (frame Y 804-844), Y 820: its entry hole in the unit's bottom stays clear of the back bend"
equation "trunk_z = 1100 mm" comment "ASSUMPTION: trunk height in B2-CASS and R1-CASS: above a ledge at about 1000 mm and its brackets, below the R1/R2 joint at Z 1255; INTERIOR keeps the ledge and screen fixings 15 mm clear"
equation "y_xc = y_bf + tray_t + felt_t + 6 mm" comment "CALCULATION: corner crossing Y 781.5: inside B2-CASS's gap (from Y 775.5) and clear of R1-CASS's back lip (from Y 788)"
equation "col_w = 217 mm" comment "DECIDED: D-61: the air column is 217 x 360 on skeleton P04"
equation "col_d = 360 mm" comment "DECIDED: D-61"
equation "col_y0 = pod_d / 2 - wall_depth" comment "CALCULATION: air column front face, against the decor back plate, Y -645"
equation "col_y1 = col_y0 + col_d" comment "CALCULATION: air column back face (into the pod), Y -285"
equation "col_x0 = x_rf - col_w" comment "CALCULATION: air column left face, X 949"
equation "col_z1 = dt_zb" comment "DECIDED: D-61: the soffit's underside, the top of the air column (Z 15 to 2120) = skeleton dt_zb, the top decor's bottom edge (named value, skeleton v4)"
equation "col_skin = 1 mm" comment "ASSUMPTION: column casing in front of its 30 mm fill (CEILING models the column)"
equation "ch_w = 24 mm" comment "ASSUMPTION: cable chase in the column's fill, 24 x 24, behind its back face and against the right wall"
equation "ch_off = 2 mm" comment "ASSUMPTION: chase clear of the right lining's felt face"
equation "y_cx = col_y1 - col_skin - ch_w / 2" comment "CALCULATION: where the trunk leaves R1-CASS's felt into the column chase, Y -298"
equation "hub_w = 180 mm" comment "DECIDED: D-61, D-70: the 180 x 180 zone for the sensor hub and controls"
equation "hub_rec = 30 mm" comment "ASSUMPTION: hub zone recessed into the column's 30 mm fill, behind its back face"
equation "hub_x0 = col_x0 + 8 mm" comment "ASSUMPTION: hub zone left edge, so it clears the chase"
equation "hub_zc = 1200 mm" comment "SOURCE: selection F3: the hub at seated eye height, Z 1200 (REQ-ELE-04)"
equation "y_kit = ( col_y1 + y_bf ) / 2" comment "CALCULATION: voice kit drop at the middle of the work wall beside the column, Y 240.5 (D-70, REQ-VCK-02)"
equation "kit_d = 60 mm" comment "ASSUMPTION: felt access hole for the kit drop, behind the screen, with a felt plug"
equation "call_z = 1450 mm" comment "ASSUMPTION: call light feed height, above the screen zone (D-70)"
equation "call_y = y_kit - 450 mm" comment "CALCULATION: call light feed at the front end of a 900 mm bar centred on the work wall, Y -209.5; its drop from the shelf runs straight down here"
equation "shelf_z = 2250 mm" comment "ASSUMPTION: light shelf height: its feed on the back wall and the call light's drop on the right wall sit behind it (Z 2200-2290 assumed; CEILING sets the shelf)"
equation "ceil_x = inner_w / 4" comment "CALCULATION: CEILING P01: the cassette's cable holes sit on the right ceiling cassette's centre, a quarter of the skeleton's inner width (X +583, PR #32)"
equation "ceil_y0 = col_y1 + 3 mm" comment "CALCULATION: CEILING P01: the ceiling cassette's front return, 3 mm behind the soffit's back face (Y -282)"
equation "ceil_y1 = y_bf - 3 mm" comment "CALCULATION: CEILING P01: the ceiling cassette's back return, 3 mm off the back lining's felt face (Y 763)"
equation "soff_y = col_y1" comment "DECIDED: D-61: the soffit's back face is flush with the column's face, Y -285"
equation "cs_h = 5.5 mm" comment "CALCULATION: half the corner slot in B2-CASS's end return, Y 776-787: inside its gap (from 775.5) and clear of R1-CASS's back lip (from 788)"
equation "dt_zb = dt_zb_Ref" comment "SOURCE: skeleton P04 dt_zb, derived (100000_P04_POD-SKELETON_CAD)"
equation "inner_w = inner_w_Ref" comment "SOURCE: skeleton P04 inner_w, derived (100000_P04_POD-SKELETON_CAD)"
equation "lx_z2 = trunk_z - 15 mm" comment "CALCULATION: upper lead exit in the unit's right side, Z 1085: more than 2 diameters (38.2) below the side's top corner relief (mechanical check C09)"
equation "lx_z1 = lx_z2 - 40 mm" comment "CALCULATION: lower lead exit, Z 1045: 40 mm below the upper one (2 diameters apart)"
equation "pod_w_Ref = 2500 mm" comment "DECIDED: D-01; conventions s4 (X = +-1250)"
equation "pod_d_Ref = 1700 mm" comment "DECIDED: D-01; conventions s4 (Y = +-850)"
equation "pod_h_Ref = 2400 mm" comment "DECIDED: D-21 (room floor to roof skin top)"
equation "glide_h_Ref = 10 mm" comment "ASSUMPTION: layout study inputs.py glide_h"
equation "band_h_Ref = 100 mm" comment "SOURCE: layout study B1 list B-BAND 100x40; inputs.py base_h"
equation "outer_t_Ref = skin_t_Ref + bond_t_Ref + frame_t_Ref" comment "DECIDED: PM ruling 2026-10-31: ACP 3 + bond line 3 + frame 40, walls and ceiling (was 43)"
equation "cav_gap_Ref = 4 mm" comment "DECIDED: D-16, D-42: the gap between the outer panel and the lining cassette in the wall and ceiling stack"
equation "cass_t_Ref = 34 mm" comment "SOURCE: layout study B1 final list L-CASS 34 (tray + 25 gap + felt 9)"
equation "stack_t_Ref = outer_t_Ref + cav_gap_Ref + cass_t_Ref" comment "CALCULATION: D-16, D-42 stack, walls and ceiling: outer panel + cavity gap + cassette (PM ruling 2026-10-31 on outer_t)"
equation "wall_depth_Ref = 1495 mm" comment "DECIDED: PM ruling pass C: side walls start at the decor back plate (Y -645), as v1 (1496)"
equation "lin_gap_Ref = 4 mm" comment "ASSUMPTION: PM ruling pass C: gap above the upper side linings so they stay floating (= the 4 mm stack gap)"
equation "seam_gap_Ref = 2.26 mm" comment "DECIDED: PM ruling 2026-10-31 (Mechanical Checker F-001, F-005): the Joints Engineer's 2.26 mm at all nine site seam types, set by a metal stop (1.5 stop washer + 0.76 rivnut head; joints register section 2.8)"
equation "fr_dz_Ref = 17 mm" comment "CALCULATION: v1 front top 2417 (v2 frame) - pod_h 2400"
equation "dt_zb_Ref = 2137 mm - fr_dz_Ref" comment "SOURCE: V1-FRONT-FACETS: DT and DR edge above the glass Z 2137"
equation "wall_z0_Ref = glide_h_Ref + band_h_Ref" comment "CALCULATION: base band top: glides + band"
equation "panel_z0_Ref = wall_z0_Ref + seam_gap_Ref" comment "CALCULATION: walls stand one seam_gap above the band top (joints register 2.8, IF-01)"
equation "wall_h_Ref = pod_h_Ref - wall_z0_Ref" comment "CALCULATION: 2290 = layout study v2_model wall_h"
equation "side_h_Ref = ( wall_h_Ref - 2 * seam_gap_Ref ) / 2" comment "CALCULATION: D-23: 2 sheets per side wall; the gap on the band and the horizontal seam (joints register 2.8)"
equation "back_oh_Ref = pod_h_Ref - outer_t_Ref - seam_gap_Ref - panel_z0_Ref" comment "CALCULATION: PM ruling 2026-10-31 (pass D, F-004): the back outer frames run up to the ceiling frame (pod_h - outer_t), less the seam_gap under it, closing the slot at the back top edge"
equation "back_ph_Ref = ( back_oh_Ref - seam_gap_Ref ) / 2" comment "CALCULATION: D-23: 4 sheets on the back, two equal rows with one seam_gap between them (joints register 2.8); the lower back linings match the lower row, as on the side walls"
equation "half_pw_Ref = ( pod_w_Ref - 2 * outer_t_Ref - 3 * seam_gap_Ref ) / 2" comment "CALCULATION: SKIN width of each back and ceiling panel: two skins and three seam_gap seams between the side frames (F-001, joints register 2.8)"
equation "inner_w_Ref = pod_w_Ref - 2 * stack_t_Ref" comment "CALCULATION: inside width between the side linings"
equation "skin_t_Ref = 3 mm" comment "DECIDED: ACP skin, walls and ceiling (D-16; PM ruling 2026-10-31 on outer_t)"
equation "bond_t_Ref = 3 mm" comment "DECIDED: bond line between the ACP and the frame (PM ruling 2026-10-31 on outer_t)"
equation "frame_t_Ref = 40 mm" comment "DECIDED: aluminium frame tube depth, walls and ceiling (PM ruling 2026-10-31 on outer_t)"
equation "z_xc = z_cf + cass_t - lip_w - grm_s / 2 - 2 mm" comment "CALCULATION: the ceiling route's crossing out of B4-CASS, Z 2330: its felt-only Ø12 hole 2 mm below the cassette's 12 mm top lip (no hole through a lip, D-69; WALL's fit check) and level with the hole in the ceiling cassette's back return"
equation "plate_ov = 8 mm" comment "ASSUMPTION: the front plate covers the felt's cut edge: 8 mm past the plain cut-out all round (WALL: the cut-out has no returns)"
equation "plate_gap = 2 mm" comment "ASSUMPTION: the front plate stands 2 mm off the felt face on four 2 mm spacers, so the floating lining never touches the unit (D-17)"
equation "fp_t = 1.5 mm" comment "PROPOSED: front plate 711002: 5052-H32 aluminium 1.5 mm, black anodised AA20 (D-67)"
equation "d1608 = ( pu_x1 ) - ( pu_x0 )"
equation "d1609 = ( y_bf + pu_d ) - ( y_bf )"
equation "d1610 = abs(pu_x0)"
equation "d1611 = abs(y_bf)"
equation "d1612 = ( pu_z0 ) * ( 1 )"
equation "d1613 = ( pu_z1 ) - ( pu_z0 )"
equation "d1615 = ( pu_x1 + pu_clr + plate_ov ) - ( pu_x0 - pu_clr - plate_ov )"
equation "d1616 = ( y_bf - plate_gap ) - ( y_bf - plate_gap - fp_t )"
equation "d1617 = abs(pu_x0 - pu_clr - plate_ov)"
equation "d1618 = abs(y_bf - plate_gap - fp_t)"
equation "d1619 = ( pu_z0 - pu_clr - plate_ov ) * ( 1 )"
equation "d1620 = ( pu_z1 + pu_clr + plate_ov ) - ( pu_z0 - pu_clr - plate_ov )"
equation "d1622 = inlet_d"
equation "d1623 = abs(inlet_x)"
equation "d1624 = abs(inlet_z)"
equation "d1625 = ( pod_d / 2 - inlet_l ) * ( 1 )"
equation "d1626 = ( pod_d / 2 ) - ( pod_d / 2 - inlet_l )"
equation "d1628 = inlet_d"
equation "d1629 = abs(inlet_x)"
equation "d1630 = abs(lan_z)"
equation "d1631 = ( pod_d / 2 - inlet_l ) * ( 1 )"
equation "d1632 = ( pod_d / 2 ) - ( pod_d / 2 - inlet_l )"
equation "d1634 = ( sl_x + 10 mm ) - ( sl_x - 10 mm )"
equation "d1635 = ( sl_y + 10 mm ) - ( sl_y - 10 mm )"
equation "d1636 = abs(sl_x - 10 mm)"
equation "d1637 = abs(sl_y - 10 mm)"
equation "d1638 = ( inlet_z - 12 mm ) * ( 1 )"
equation "d1639 = ( pu_z0 ) - ( inlet_z - 12 mm )"
equation "d1641 = ( lt_x + pk_h ) - ( lt_x - pk_h )"
equation "d1642 = ( y_bg + rt_h ) - ( y_bg - rt_h )"
equation "d1643 = abs(lt_x - pk_h)"
equation "d1644 = abs(y_bg - rt_h)"
equation "d1645 = ( cut_z1 + tray_t ) * ( 1 )"
equation "d1646 = ( cut_z1 + tray_t + 80 mm ) - ( cut_z1 + tray_t )"
equation "d1648 = ( lt_x + rt_h ) - ( lt_x - rt_h )"
equation "d1649 = ( y_bg + rt_h ) - ( y_bg - rt_h )"
equation "d1650 = abs(lt_x - rt_h)"
equation "d1651 = abs(y_bg - rt_h)"
equation "d1652 = ( cut_z1 + tray_t + 80 mm ) * ( 1 )"
equation "d1653 = ( z_b2t - tray_t ) - ( cut_z1 + tray_t + 80 mm )"
equation "d1655 = grm_d"
equation "d1656 = abs(lt_x)"
equation "d1657 = abs(y_bg)"
equation "d1658 = ( z_b2t - tray_t ) * ( 1 )"
equation "d1659 = ( z_b4b + tray_t ) - ( z_b2t - tray_t )"
equation "d1661 = ( lt_x + pk_h ) - ( lt_x - pk_h )"
equation "d1662 = ( y_bg + rt_h ) - ( y_bg - rt_h )"
equation "d1663 = abs(lt_x - pk_h)"
equation "d1664 = abs(y_bg - rt_h)"
equation "d1665 = ( z_b4b + tray_t ) * ( 1 )"
equation "d1666 = ( z_b4b + tray_t + pk_l ) - ( z_b4b + tray_t )"
equation "d1668 = ( lt_x + rt_h ) - ( lt_x - rt_h )"
equation "d1669 = ( y_bg + rt_h ) - ( y_bg - rt_h )"
equation "d1670 = abs(lt_x - rt_h)"
equation "d1671 = abs(y_bg - rt_h)"
equation "d1672 = ( z_b4b + tray_t + pk_l ) * ( 1 )"
equation "d1673 = ( shelf_z - 60 mm ) - ( z_b4b + tray_t + pk_l )"